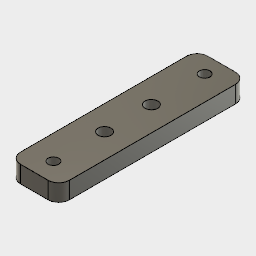
Handle_Bracket_v1 (Autodesk Fusion 360 design; units mm, degrees)
Autodesk Fusion 360 part; units mm, degrees
sketch "Sketch1" plane through (0, 0, 0) normal (0, 1, 0) x (1, 0, 0)
  line L0 (4, 45.0073) -> (17, 45.0073)
  line L1 (22, 40.0073) -> (22, -38)
  line L2 (17, -43) -> (4, -43)
  line L3 (-1, -38) -> (-1, 40.0073)
  circle A0 centre (10.5, -10) radius 3
  circle A1 centre (10.5, 12) radius 3
  circle A2 centre (10.5, -34) radius 2.5
  circle A3 centre (10.5, 37) radius 2.5
  arc A4 (-1, -38) -> (4, -43) centre (4, -38) ccw
  arc A5 (17, -43) -> (22, -38) centre (17, -38) ccw
  arc A6 (22, 40.0073) -> (17, 45.0073) centre (17, 40.0073) ccw
  arc A7 (4, 45.0073) -> (-1, 40.0073) centre (4, 40.0073) ccw
  dimension "d1" = 5
  dimension "d2" = 5
  dimension "d3" = 6
  dimension "d5" = 6
  dimension "d6" = 5
  measures "d1" diameter of A3
  measures "d2" diameter of A2
  measures "d3" diameter of A0
  measures "d5" diameter of A1
  measures "d6" radius of A4
extrude "Extrude1" add sketch "Sketch1" along normal blind 8
